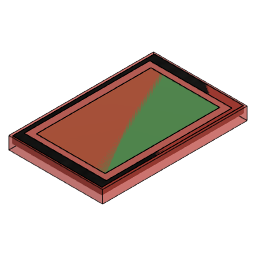
Project_MO_V1_Manufacturing_Release (Autodesk Fusion 360 archive; units mm, degrees)
design "Display"
part number: 2026-08-24-19-36-23-458
Autodesk Fusion 360 part; units mm, degrees
sketch "Esboço1" plane through (0, 0, 0) normal (0, 0, 1) x (1, 0, 0)
  line L0 (42, 66.75) -> (-42, 66.75)
  line L1 (-42, 66.75) -> (-42, -66.75)
  line L2 (-42, -66.75) -> (42, -66.75)
  line L3 (42, -66.75) -> (42, 66.75)
  line L4 (42, 66.75) -> (-42, -66.75) construction
  line L5 (-42, 66.75) -> (42, -66.75) construction
  dimension "d10" = 84
  dimension "d11" = 133.5
  constraint horizontal L0
  constraint perpendicular L0 L1
  constraint parallel L0 L2
  constraint parallel L1 L3
  constraint coincident L4 origin
  constraint coincident L5 origin
  measures "d10" distance of L1.end L2.end
  measures "d11" distance of L0.end L1.end
extrude "Extrusão1" add sketch "Esboço1" along normal blind 6.2 makes body 1
sketch "Esboço2" plane through (0, 0, 6.2) normal (0, 0, 1) x (-1, 0, 0)
  line L0 (-42, 66.75) -> (-42, -66.75)
  line L1 (-42, -66.75) -> (42, -66.75)
  line L2 (42, -66.75) -> (42, 66.75)
  line L3 (42, 66.75) -> (-42, 66.75)
  line L4 (-38.75, 59.25) -> (38.75, 59.25)
  line L5 (38.75, 59.25) -> (38.75, -59.25)
  line L6 (38.75, -59.25) -> (-38.75, -59.25)
  line L7 (-38.75, -59.25) -> (-38.75, 59.25)
  line L8 (-38.75, 59.25) -> (38.75, -59.25) construction
  line L9 (38.75, 59.25) -> (-38.75, -59.25) construction
  dimension "d14" = 77.5
  dimension "d15" = 118.5
  constraint horizontal L4
  constraint perpendicular L4 L5
  constraint parallel L4 L6
  constraint parallel L5 L7
  constraint coincident L8 origin
  constraint coincident L9 origin
  measures "d14" distance of L5.end L6.end
  measures "d15" distance of L4.end L5.end
extrude "Extrusão2" cut sketch "Esboço2" against normal blind 0.01 contours L4 L5 L6 L7 bodies 1
sketch "Esboço3" plane through (0, 0, 6.19) normal (0, 0, 1) x (-1, 0, 0)
  line L0 (-38.75, -59.25) -> (38.75, -59.25)
  line L1 (38.75, -59.25) -> (38.75, 59.25)
  line L2 (38.75, 59.25) -> (-38.75, 59.25)
  line L3 (-38.75, 59.25) -> (-38.75, -59.25)
  line L4 (32.4, 54) -> (-32.4, 54)
  line L5 (-32.4, 54) -> (-32.4, -54)
  line L6 (-32.4, -54) -> (32.4, -54)
  line L7 (32.4, -54) -> (32.4, 54)
  line L8 (32.4, 54) -> (-32.4, -54) construction
  line L9 (-32.4, 54) -> (32.4, -54) construction
  dimension "d18" = 64.8
  dimension "d19" = 108
  constraint horizontal L4
  constraint perpendicular L4 L5
  constraint parallel L4 L6
  constraint parallel L5 L7
  constraint coincident L8 origin
  constraint coincident L9 origin
  measures "d18" distance of L5.end L6.end
  measures "d19" distance of L4.end L5.end
extrude "Extrusão3" add sketch "Esboço3" along normal blind 0.01 contours L4 L5 L6 L7 bodies 1
sketch "Esboço5" plane through (0, 0, 0) normal (0, 0, 1) x (1, 0, 0)
  line L0 (-44.25, 68.25) -> (44.25, 68.25)
  line L1 (44.25, 68.25) -> (44.25, -68.25)
  line L2 (44.25, -68.25) -> (-44.25, -68.25)
  line L3 (-44.25, -68.25) -> (-44.25, 68.25)
  line L4 (-44.25, 68.25) -> (44.25, -68.25) construction
  line L5 (44.25, 68.25) -> (-44.25, -68.25) construction
  dimension "d26" = 88.5
  dimension "d27" = 136.5
  constraint horizontal L0
  constraint perpendicular L0 L1
  constraint parallel L0 L2
  constraint parallel L1 L3
  constraint coincident L4 origin
  constraint coincident L5 origin
  measures "d26" distance of L1.end L2.end
  measures "d27" distance of L0.end L1.end
extrude "Extrusão5" add sketch "Esboço5" along normal blind 12 separate body makes body 2
move_body "Alinhar1" bodies 2 to x (1, 0, 0) y (0, 1, 0) z (0, 0, 1) at (0, 0, -5.8)
equation "DisplayWidht = 133.5 mm"
equation "DisplayHeight = 84 mm"
equation "DisplayDepth = 6.2 mm"
equation "DisplayClearance = 2.25 mm"
equation "DisplayClearanceDepth = 12 mm"
equation "VisibleWidth = 118.5 mm"
equation "VisibleHeight = 77.5 mm"
equation "ActiveWidth = 108 mm"
equation "ActiveHeight = 64.8 mm"
equation "d10 = DisplayHeight"
equation "d11 = DisplayWidht"
equation "d12 = DisplayDepth"
equation "d14 = VisibleHeight"
equation "d15 = VisibleWidth"
equation "d18 = ActiveHeight"
equation "d19 = ActiveWidth"
named bodies: "Nextion_Physical", "Clearance"
